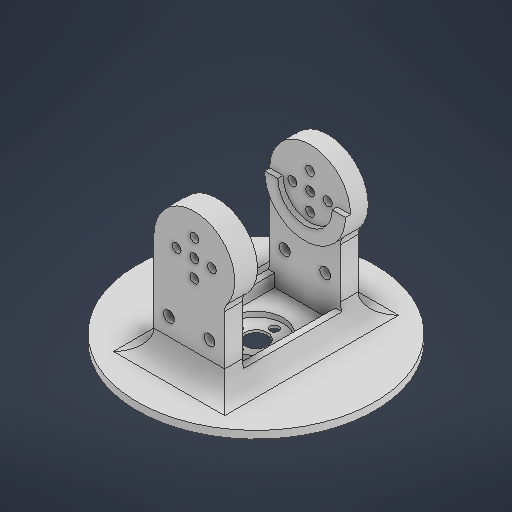
# Autodesk Inventor part: BaseS2P1V4
Saved by Autodesk Inventor 2027 (Build 310192060, 192F)
## iProperties
Created: 2026-08-06
Part Number: BaseS2P1V4
Material: Generic
Document SubType Name: Modeling
Designer: jose2
Density: 1 g/cm^3
Appearance: Default
Author: jose2
Autodesk Inventor part; units mm, degrees
ref_plane "YZ Plane" through (0, 0, 0) normal (1, 0, 0) x (0, 1, 0)
ref_plane "XZ Plane" through (0, 0, 0) normal (0, 1, 0) x (-1, 0, 0)
ref_plane "XY Plane" through (0, 0, 0) normal (0, 0, 1) x (1, 0, 0)
sketch "Sketch1" plane through (0, 0, 0) normal (0, 1, 0) x (-1, 0, 0)
  circle A0 centre (0, 0) radius 47
  dimension "d0" = 94
  constraints: 1 centre point, 1 coincident
  measures "d0" diameter of A0
extrude "Extrusion1" add sketch "Sketch1" along normal blind 3
sketch "Sketch2" plane through (0, 3, 0) normal (0, 1, 0) x (1, 0, 0)
  circle A0 centre (0, 0) radius 10.75
  circle A1 centre (0, 0) radius 1.5
  circle A2 centre (0, 7.25) radius 1.75
  circle A3 centre (-7.25, 0) radius 1.75
  circle A4 centre (0, -7.25) radius 1.75
  circle A5 centre (7.25, 0) radius 1.75
  circle A6 centre (0, 0) radius 4.6
  dimension "d3" = 21.5
  dimension "d4" = 3
  dimension "d5" = 3.5
  dimension "d6" = 4
  dimension "d9" = 360
  dimension "d11" = 9.2
  constraints: 7 centre point, 3 coincident, 9 other
  measures "d3" diameter of A0
  measures "d4" diameter of A1
  measures "d5" diameter of A2
  measures "d11" diameter of A6
extrude "Extrusion2" cut sketch "Sketch2" against normal blind 3 contours A1
extrude "Extrusion3" cut sketch "Sketch2" against normal blind 3 contours A6
extrude "Extrusion4" cut sketch "Sketch2" against normal blind 2 contours A0
extrude "Extrusion7" cut sketch "Sketch2" against normal up to next contours A2 | A3 | A4 | A5
sketch "Sketch5" plane through (0, 3, 0) normal (0, 1, 0) x (1, 0, 0)
  line L0 (-10, 19.4) -> (10, 19.4)
  line L1 (10, 19.4) -> (10, -19.4)
  line L2 (10, -19.4) -> (-10, -19.4)
  line L3 (-10, -19.4) -> (-10, 19.4)
  line L4 (-10, 19.4) -> (10, -19.4) construction
  line L5 (10, 19.4) -> (-10, -19.4) construction
  line L6 (10, 19.4) -> (-10, 19.4)
  line L7 (-10, 19.4) -> (-10, 26.4)
  line L8 (-10, 26.4) -> (10, 26.4)
  line L9 (10, 26.4) -> (10, 19.4)
  line L10 (-10, -19.4) -> (10, -19.4)
  line L11 (10, -19.4) -> (10, -26.4)
  line L12 (10, -26.4) -> (-10, -26.4)
  line L13 (-10, -26.4) -> (-10, -19.4)
  line L14 (-10, 26.4) -> (-14, 26.4)
  line L15 (-14, 26.4) -> (-14, 19.4)
  line L16 (-14, 19.4) -> (-10, 19.4)
  line L17 (-10, 19.4) -> (-10, 26.4)
  line L18 (10, 26.4) -> (14, 26.4)
  line L19 (14, 26.4) -> (14, 19.4)
  line L20 (14, 19.4) -> (10, 19.4)
  line L21 (10, 19.4) -> (10, 26.4)
  line L22 (-10, -19.4) -> (-14, -19.4)
  line L23 (-14, -19.4) -> (-14, -26.4)
  line L24 (-14, -26.4) -> (-10, -26.4)
  line L25 (-10, -26.4) -> (-10, -19.4)
  line L26 (10, -19.4) -> (14, -19.4)
  line L27 (14, -19.4) -> (14, -26.4)
  line L28 (14, -26.4) -> (10, -26.4)
  line L29 (10, -26.4) -> (10, -19.4)
  line L30 (14, 19.4) -> (12, 19.4)
  line L31 (12, 19.4) -> (12, -19.4)
  line L32 (12, -19.4) -> (14, -19.4)
  line L33 (14, -19.4) -> (14, 19.4)
  line L34 (-14, 19.4) -> (-12, 19.4)
  line L35 (-12, 19.4) -> (-12, -19.4)
  line L36 (-12, -19.4) -> (-14, -19.4)
  line L37 (-14, -19.4) -> (-14, 19.4)
  point P0 (0, 0)
  point P1 (10, -26.4)
  point P2 (-10, -26.4)
  point P3 (14, -22.9)
  point P4 (-14, -22.9)
  dimension "d33" = 38.8
  dimension "d34" = 7
  dimension "d35" = 7
  dimension "d49" = 4
  dimension "d50" = 4
  dimension "d53" = 7
  dimension "d76" = 28
  dimension "d77" = 52.8
  constraints: 76 end point, 18 parallel, 9 horizontal, 9 perpendicular, 6 midpoint, 4 point on line
  measures "d33" distance of L0.end L1.end
  measures "d34" distance of L6.end L7.end
  measures "d35" distance of L10.end L11.end
  measures "d49" distance of L16.end L15.end
  measures "d50" distance of L19.end L20.end
  measures "d53" distance of L26.end L27.end
  measures "d76" distance of point (14, -22.9) point (-14, -22.9)
  measures "d77" distance between parallel lines of L8 L12
extrude "Extrusion8" add sketch "Sketch5" along normal blind 40 contours L7 L8 L9 L0 | L16 L15 L14 L7 | L9 L18 L19 L20 | L2 L11 L12 L13 | L13 L24 L23 L22 | L26 L27 L28 L11
extrude "Extrusion10" add sketch "Sketch5" along normal blind 5 contours L35 L22 L37 L16 | L20 L33 L26 L31
sketch "Sketch8" plane through (-14, 3, 26.4) normal (0, 0, 1) x (1, 0, 0)
  point P0 (14, -3)
sketch "Sketch9" plane through (-14, 3, 26.4) normal (0, 0, 1) x (1, 0, 0)
  line L0 (0, 40) -> (28, 40) projected
  circle A0 centre (16, 40) radius 16
  point P0 (14, -3)
  dimension "d56" = 16
  constraints: 1 horizontal alignment, 1 point on line, 2 other
  measures "d56" distance of point (16, 40) L0.start
extrude "Extrusion11" add sketch "Sketch9" against normal blind 7
sketch "Sketch10" plane through (14, 3, -26.4) normal (0, 0, -1) x (-1, 0, 0)
  line L0 (28, 0) -> (28, 40) projected
  line L1 (28, 40) -> (12, 40)
  line L2 (28, 40) -> (0, 40) projected
  circle A0 centre (12, 40) radius 16
  point P0 (14, -3)
  dimension "d57" = 16
  constraints: 2 end point, 1 coincident, 1 horizontal alignment, 1 point on line, 2 other
  measures "d57" distance of L0.end L1.end
extrude "Extrusion12" add sketch "Sketch10" against normal blind 7
fillet "Fillet1" radius 5 2 edges at (14, 32.417, -22.9) (14, 32.417, 22.9)
sketch "Sketch11" plane through (-14, 3, 26.4) normal (0, 0, 1) x (1, 0, 0)
  arc A0 (28.9524, 30.6066) -> (0, 40) centre (16, 40) ccw projected
  circle A1 centre (16, 40) radius 16
  circle A2 centre (16, 40) radius 1.75
  circle A3 centre (16, 40) radius 7
  circle A4 centre (23, 40) radius 1.75
  circle A5 centre (16, 47) radius 1.75
  circle A6 centre (9, 40) radius 1.75
  circle A7 centre (16, 33) radius 1.75
  line L0 (28, 0) -> (0, 0) projected
  line L1 (0, 0) -> (6, 0)
  line L2 (6, 0) -> (6, 15)
  line L3 (6, 15) -> (0, 15)
  line L4 (0, 15) -> (0, 0)
  line L5 (28, 0) -> (22, 0)
  line L6 (22, 0) -> (22, 15)
  line L7 (22, 15) -> (28, 15)
  line L8 (28, 15) -> (28, 0)
  circle A8 centre (6, 15) radius 2.15
  circle A9 centre (22, 15) radius 2.15
  point P0 (14, -3)
  dimension "d62" = 14
  dimension "d61" = 3.5
  dimension "d63" = 3.5
  dimension "d66" = 360
  dimension "d68" = 6
  dimension "d69" = 15
  dimension "d70" = 6
  dimension "d71" = 15
  dimension "d72" = 4.3
  dimension "d73" = 4.3
  constraints: 16 end point, 8 centre point, 5 coincident, 4 parallel, 2 horizontal, 2 perpendicular, 1 horizontal alignment, 11 other
  measures "d61" diameter of A2
  measures "d63" diameter of A4
  measures "d68" distance of L3.end L2.end
  measures "d69" distance of L2.end L1.end
  measures "d70" distance of L6.end L7.end
  measures "d71" distance of L5.end L6.end
  measures "d72" diameter of A8
  measures "d73" diameter of A9
extrude "Extrusion13" cut sketch "Sketch11" against normal blind 100 contours A2 | A3 A4 | A3 A4 | A5 A3 | A3 A5 | A7 A3 | A3 A7 | A6 A3 | A3 A6 | A9 L7 L6 | L6 L7 A9 | A8 L3 L2 | L2 L3 A8
sketch "Sketch12" plane through (-14, 3, 26.4) normal (0, 0, 1) x (1, 0, 0)
  point P0 (14, -3)
fillet "Fillet2" radius 8 4 edges at (0, 3, 26.4) (14, 3, 0) (0, 3, -26.4) (-14, 3, 0)
sketch "Sketch13" plane through (12, 3, 19.4) normal (0, 0, -1) x (-1, 0, 0)
  point P0 (12, -3)
sketch "Sketch14" plane through (12, 3, 19.4) normal (0, 0, -1) x (-1, 0, 0)
  circle A0 centre (10, 40) radius 1.75 projected
  circle A1 centre (10, 40) radius 10.75
  circle A2 centre (10, 40) radius 16
  point P0 (12, -3)
  dimension "d79" = 21.5
  constraints: 2 centre point, 2 coincident
  measures "d79" diameter of A1
extrude "Extrusion14" add sketch "Sketch14" along normal blind 2 contours A2
sketch "Sketch15" plane through (-12, 3, -19.4) normal (0, 0, 1) x (1, 0, 0)
  circle A0 centre (14, 40) radius 1.75 projected
  circle A1 centre (14, 40) radius 10.75
  circle A2 centre (14, 40) radius 16
  line L0 (3.25, 40) -> (-2, 40)
  line L1 (24.75, 40) -> (30, 40)
  point P0 (12, -3)
  dimension "d82" = 21.5
  dimension "d83" = 32
  constraints: 4 end point, 4 point on circle, 2 centre point, 2 coincident, 2 point on line, 1 horizontal
  measures "d82" diameter of A1
  measures "d83" diameter of A2
extrude "Extrusion15" add sketch "Sketch15" along normal blind 2 contours L1 A2 L0 A1 picked at (27.9909, 37.8661)
body "Solid1"
